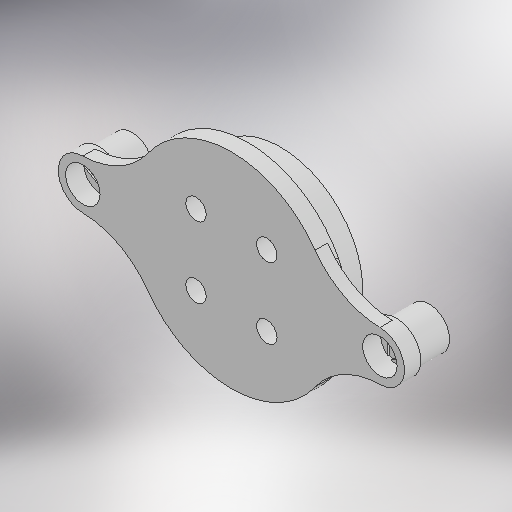
# Autodesk Inventor part: center-half
Saved by Autodesk Inventor 2025.3 (Build 293356030, 356C)
## iProperties
Created: 2026-05-05
Part Number: center-half
Material: 一般
Document SubType Name: Modeling
Designer: ibuki_ono
Density: 1 g/cm^3
Appearance: 既定
Author: ibuki_ono
## iProperties of the stored document center-half_3D プリント.ipt
Created: 2026-05-08
Part Number: center-half_3D プリント
Material: 一般
Document SubType Name: Modeling
Designer: ibuki_ono
Density: 1 g/cm^3
Appearance: 既定
Author: ibuki_ono
Autodesk Inventor part; units mm, degrees
ref_plane "YZ Plane" through (0, 0, 0) normal (1, 0, 0) x (0, 1, 0)
ref_plane "XZ Plane" through (0, 0, 0) normal (0, 1, 0) x (-1, 0, 0)
ref_plane "XY Plane" through (0, 0, 0) normal (0, 0, 1) x (1, 0, 0)
sketch "スケッチ1" plane through (0, 0, 0) normal (0, 0, 1) x (1, 0, 0)
  circle A0 centre (0, 0) radius 12.5
  line L0 (-18.1, 0) -> (18.1, 0) construction
  line L1 (-18.1, -3) -> (18.1, -3)
  line L2 (18.1, 3) -> (-18.1, 3)
  arc A1 (-18.1, 3) -> (-18.1, -3) centre (-18.1, 0) ccw
  arc A2 (18.1, -3) -> (18.1, 3) centre (18.1, 0) ccw
  line L3 (0, 0) -> (36.2, 0) construction
  point P0 (-12.1347, -3)
  point P1 (12.1347, -3)
  point P2 (12.1347, 3)
  point P3 (-12.1347, 3)
  dimension "d0" = 25
  dimension "d1" = 18.1
  dimension "d2" = 0
  dimension "d3" = 6
  constraints: 10 end point, 4 point on circle, 4 tangent, 3 centre point, 2 horizontal, 1 coincident, 1 collinear, 1 midpoint, 1 parallel
  measures "d0" diameter of A0
  measures "d1" distance of L3.start L0.end
  measures "d2" distance between parallel lines of L0 L3
  measures "d3" diameter of A2
extrude "押し出し1" add sketch "スケッチ1" along normal mid plane 2
sketch "スケッチ4" plane through (0, 0, -1) normal (0, 0, -1) x (-1, 0, 0)
  arc A0 (18.1, -3) -> (18.1, 3) centre (18.1, 0) ccw projected
  arc A1 (-18.1, 3) -> (-18.1, -3) centre (-18.1, 0) ccw projected
  line L0 (12.1347, -3) -> (18.1, -3) projected
  line L1 (18.1, 3) -> (12.1347, 3) projected
  line L2 (-12.1347, 3) -> (-18.1, 3) projected
  line L3 (-18.1, -3) -> (-12.1347, -3) projected
  circle A2 centre (18.1, 0) radius 3
  circle A3 centre (-18.1, 0) radius 3
  line L4 (12.1347, 3) -> (18.1, 3) projected
  circle A4 centre (0, 0) radius 12.5
  circle A5 centre (18.1, 0) radius 7
  circle A6 centre (-18.1, 0) radius 7
  point P0 (-12.1347, -3)
  point P1 (-12.1347, 3)
  point P2 (18.1, 3)
  point P3 (-12.0127, 3.4561)
  point P4 (-12.0127, -3.4561)
  point P5 (12.0127, 3.4561)
  point P6 (12.0127, -3.4561)
  dimension "d21" = 14
  dimension "d22" = 14
  constraints: 5 coincident, 3 centre point, 1 concentric, 6 other
  measures "d21" diameter of A5
  measures "d22" diameter of A6
extrude "押し出し4" cut sketch "スケッチ4" against normal blind 0.5 contours L0 A4 L1 A2 | A4 A5 | A4 A6 | L3 A3 L2 A4
sketch "スケッチ5" plane through (-18.1, 0, -1) normal (0, 0, -1) x (-1, 0, 0)
  circle A0 centre (0, 0) radius 3 projected
  circle A1 centre (-36.2, 0) radius 3 projected
  point P0 (-18.1, 0)
hole "穴1" at (-18.1, 0, -1) at (18.1, 0, -1) direction (0, 0, 1) diameter 2.5 end through all
sketch "スケッチ6" plane through (0, 0, -1) normal (0, 0, -1) x (-1, 0, 0)
  circle A0 centre (0, 0) radius 10
  dimension "d23" = 20
  constraints: 1 centre point, 1 coincident
  measures "d23" diameter of A0
extrude "押し出し5" add sketch "スケッチ6" along normal blind 4
sketch "スケッチ7" plane through (18.1, 0, -1) normal (0, 0, -1) x (0, -1, 0)
  circle A0 centre (0, 0) radius 1.25 projected
  circle A1 centre (0, 36.2) radius 1.25 projected
  circle A2 centre (0, 0) radius 2.5
  circle A3 centre (0, 36.2) radius 2.5
  point P0 (0, 18.1)
  dimension "d26" = 5
  dimension "d27" = 5
  constraints: 2 centre point, 2 coincident
  measures "d26" diameter of A2
  measures "d27" diameter of A3
extrude "押し出し6" add sketch "スケッチ7" along normal up to surface (4 mm away)
fillet "フィレット1" radius 5 4 edges at (12.0127, -3.4561, -0.75) (12.0127, 3.4561, -0.75) (-12.0127, -3.4561, -0.75) (-12.0127, 3.4561, -0.75)
fillet "フィレット2" radius 10 4 edges at (12.1347, -3, 0.25) (12.1347, 3, 0.25) (-12.1347, -3, 0.25) (-12.1347, 3, 0.25)
sketch "スケッチ8" plane through (0, 0, -5) normal (0, 0, -1) x (-1, 0, 0)
  circle A0 centre (0, 0) radius 6.1 construction
  line L0 (4.3134, 4.3134) -> (-4.3134, 4.3134) construction
  line L1 (-4.3134, 4.3134) -> (-4.3134, -4.3134) construction
  line L2 (-4.3134, -4.3134) -> (4.3134, -4.3134) construction
  line L3 (4.3134, -4.3134) -> (4.3134, 4.3134) construction
  line L4 (4.3134, 4.3134) -> (-4.3134, -4.3134) construction
  line L5 (-4.3134, 4.3134) -> (4.3134, -4.3134) construction
  point P0 (4.3134, -4.3134)
  dimension "d32" = 12.2
  constraints: 12 end point, 4 coincident, 2 midpoint, 2 parallel, 2 perpendicular, 2 point on circle, 1 centre point, 1 horizontal
  measures "d32" diameter of A0
hole "穴2" at (-4.3134, -4.3134, -5) at (-4.3134, 4.3134, -5) at (4.3134, 4.3134, -5) at (4.3134, -4.3134, -5) direction (0, 0, 1) diameter 2.5 end through all
sketch "スケッチ9" plane through (0, 0, 1) normal (0, 0, 1) x (1, 0, 0)
  circle A0 centre (18.1, 0) radius 1.25 projected
  circle A1 centre (-18.1, 0) radius 1.25 projected
  circle A2 centre (-18.1, 0) radius 2.1
  circle A3 centre (18.1, 0) radius 2.1
  point P0 (0, 0)
  dimension "d40" = 4.2
  dimension "d41" = 4.2
  constraints: 2 centre point, 2 coincident
  measures "d40" diameter of A2
  measures "d41" diameter of A3
extrude "押し出し7" cut sketch "スケッチ9" against normal blind 2.2
sketch "スケッチ10" plane through (-18.1, 0, -1.2) normal (0, 0, 1) x (1, 0, 0)
  circle A0 centre (0, 0) radius 2.1 projected
  circle A1 centre (0, 0) radius 1.25 projected
  line L0 (1.25, 1.6875) -> (1.25, -1.6875)
  line L1 (0.8364, -1.9263) -> (-2.0864, -0.2388)
  line L2 (0.8364, -1.9263) -> (4.2113, -1.9263) construction
  circle A2 centre (0, 0) radius 2.1 projected
  line L3 (-2.0864, 0.2388) -> (0.8364, 1.9263)
  line L4 (-2.0864, 0.2388) -> (1.2885, 0.2388) construction
  circle A3 centre (0, 0) radius 1.25 projected
  point P0 (18.1, 0)
  point P1 (-0.625, 1.0825)
  point P2 (-2.0864, 0.2388)
  point P3 (-2.0864, -0.2388)
  point P4 (-0.625, -1.0825)
  point P5 (0.8364, 1.9263)
  point P6 (1.25, 0)
  dimension "d44" = 150
  dimension "d45" = 30
  dimension "d46" = 60
  constraints: 10 end point, 6 point on circle, 3 tangent, 2 equal length, 2 horizontal
  measures "d44" angle of L2 L1
  measures "d45" angle of L4 L3
  measures "d46" angle of L3 L0
extrude "押し出し8" cut sketch "スケッチ10" against normal blind 0.2 contours L0 A1 L3 A0 | A0 L1 A1 L0 | L3 A1 L1 A0
mirror "ミラー1" about plane through (0, 0, 0) normal (1, 0, 0) of "押し出し8"
equation "\"d26\" = d27"
equation "\"d40\" = d41"
